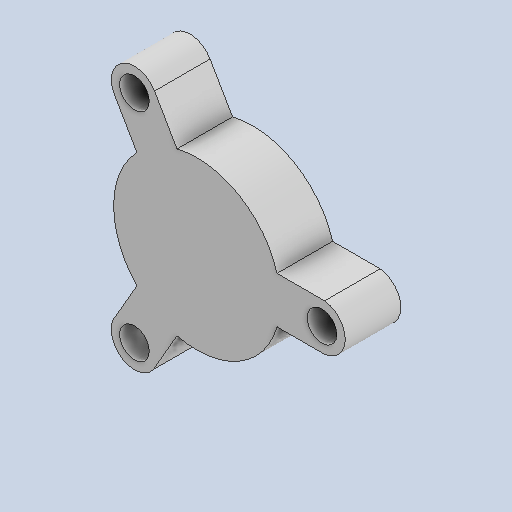
# Autodesk Inventor part: J1_J2_GASKET
Saved by Autodesk Inventor 2025.3 (Build 293356000, 356)
## iProperties
Created: 2026-08-11
Part Number: J1_J2_GASKET
Material: 常规
Document SubType Name: Modeling
Designer: Admin
Density: 1 g/cm^3
Appearance: 默认
Author: Admin
Autodesk Inventor part; units mm, degrees
ref_plane "YZ Plane" through (0, 0, 0) normal (1, 0, 0) x (0, 1, 0)
ref_plane "XZ Plane" through (0, 0, 0) normal (0, 1, 0) x (-1, 0, 0)
ref_plane "XY Plane" through (0, 0, 0) normal (0, 0, 1) x (1, 0, 0)
sketch "草图1" plane through (0, 0, 0) normal (0, 0, 1) x (1, 0, 0)
  line L0 (8.6458, 2.5) -> (13.784, 2.5) projected
  arc A0 (13.784, 2.5) -> (15.6853, 5.1207) centre (13.784, 4.5) ccw projected
  arc A1 (15.6853, 5.1207) -> (-3.408, 16.1442) centre (0, 0) ccw projected
  arc A2 (-3.408, 16.1442) -> (-4.727, 13.1873) centre (-2.9949, 14.1873) ccw projected
  line L1 (-4.727, 13.1873) -> (-2.1578, 8.7375) projected
  arc A3 (8.6458, 2.5) -> (-2.1578, 8.7375) centre (0, 0) ccw projected
  line L2 (-6.488, 6.2375) -> (-9.0571, 10.6873) projected
  arc A4 (-9.0571, 10.6873) -> (-12.2773, 11.0235) centre (-10.7891, 9.6873) ccw projected
  arc A5 (-12.2773, 11.0235) -> (-12.2773, -11.0235) centre (0, 0) ccw projected
  arc A6 (-12.2773, -11.0235) -> (-9.0571, -10.6873) centre (-10.7891, -9.6873) ccw projected
  line L3 (-9.0571, -10.6873) -> (-6.488, -6.2375) projected
  arc A7 (-6.488, 6.2375) -> (-6.488, -6.2375) centre (0, 0) ccw projected
  arc A8 (-4.727, -13.1873) -> (-3.408, -16.1442) centre (-2.9949, -14.1873) ccw projected
  arc A9 (-3.408, -16.1442) -> (15.6853, -5.1207) centre (0, 0) ccw projected
  arc A10 (15.6853, -5.1207) -> (13.784, -2.5) centre (13.784, -4.5) ccw projected
  line L4 (13.784, -2.5) -> (8.6458, -2.5) projected
  arc A11 (-2.1578, -8.7375) -> (8.6458, -2.5) centre (0, 0) ccw projected
  line L5 (-2.1578, -8.7375) -> (-4.727, -13.1873) projected
  line L6 (17.0359, 20.15) -> (-17.0359, 20.15) projected
  line L7 (40, -21.85) -> (15, -21.85) projected
  line L8 (-40, 26.15) -> (-40, -21.85) projected
  circle A12 centre (-6.75, 11.6913) radius 2.5
  circle A13 centre (-6.75, -11.6913) radius 2.5161
  circle A14 centre (13.5, 0) radius 2.5161
  circle A15 centre (-6.75, -11.6913) radius 1.6 projected
  circle A16 centre (13.5, 0) radius 1.6 projected
  circle A17 centre (-6.75, 11.6913) radius 1.6 projected
  arc A18 (10.0359, -21.85) -> (12.0154, -20.1357) centre (10.0359, -19.85) ccw projected
  line L9 (10.0359, -21.85) -> (-10.0359, -21.85) projected
  arc A19 (-12.0154, -20.1357) -> (-10.0359, -21.85) centre (-10.0359, -19.85) ccw projected
  arc A20 (-12.0154, -20.1357) -> (-15, -20.35) centre (-13.5, -20.35) ccw projected
  line L10 (-15, -20.35) -> (-15, -21.85) projected
  line L11 (40, -21.85) -> (40, 26.15) projected
  line L12 (15, -21.85) -> (15, -20.35) projected
  arc A21 (15, -20.35) -> (12.0154, -20.1357) centre (13.5, -20.35) ccw projected
  line L13 (-22, 26.15) -> (-40, 26.15) projected
  line L14 (40, 26.15) -> (22, 26.15) projected
  arc A22 (-17.0359, 20.15) -> (-19.0154, 18.4357) centre (-17.0359, 18.15) ccw projected
  arc A23 (19.0154, 18.4357) -> (17.0359, 20.15) centre (17.0359, 18.15) ccw projected
  arc A24 (19.0154, 18.4357) -> (22, 18.65) centre (20.5, 18.65) ccw projected
  line L15 (22, 18.65) -> (22, 26.15) projected
  line L16 (-15, -21.85) -> (-40, -21.85) projected
  line L17 (-22, 26.15) -> (-22, 18.65) projected
  arc A25 (-22, 18.65) -> (-19.0154, 18.4357) centre (-20.5, 18.65) ccw projected
  point P0 (0, 0)
  point P1 (40, 20.15)
  point P2 (-4.5849, 12.9413)
  point P3 (-8.9151, 10.4413)
  point P4 (-9.0571, -10.6873)
  point P5 (13.784, -2.5)
  point P6 (22, 20.15)
  point P7 (-22, 20.15)
  constraints: 1 centre point, 1 tangent, 6 other
extrude "拉伸1" add sketch "草图1" along normal blind 6 contours L0 A14 L4 A11 L5 A13 L3 A7 L2 A12 L1 A3 | L0 A14 L4 | A12 | L5 A13 L3
